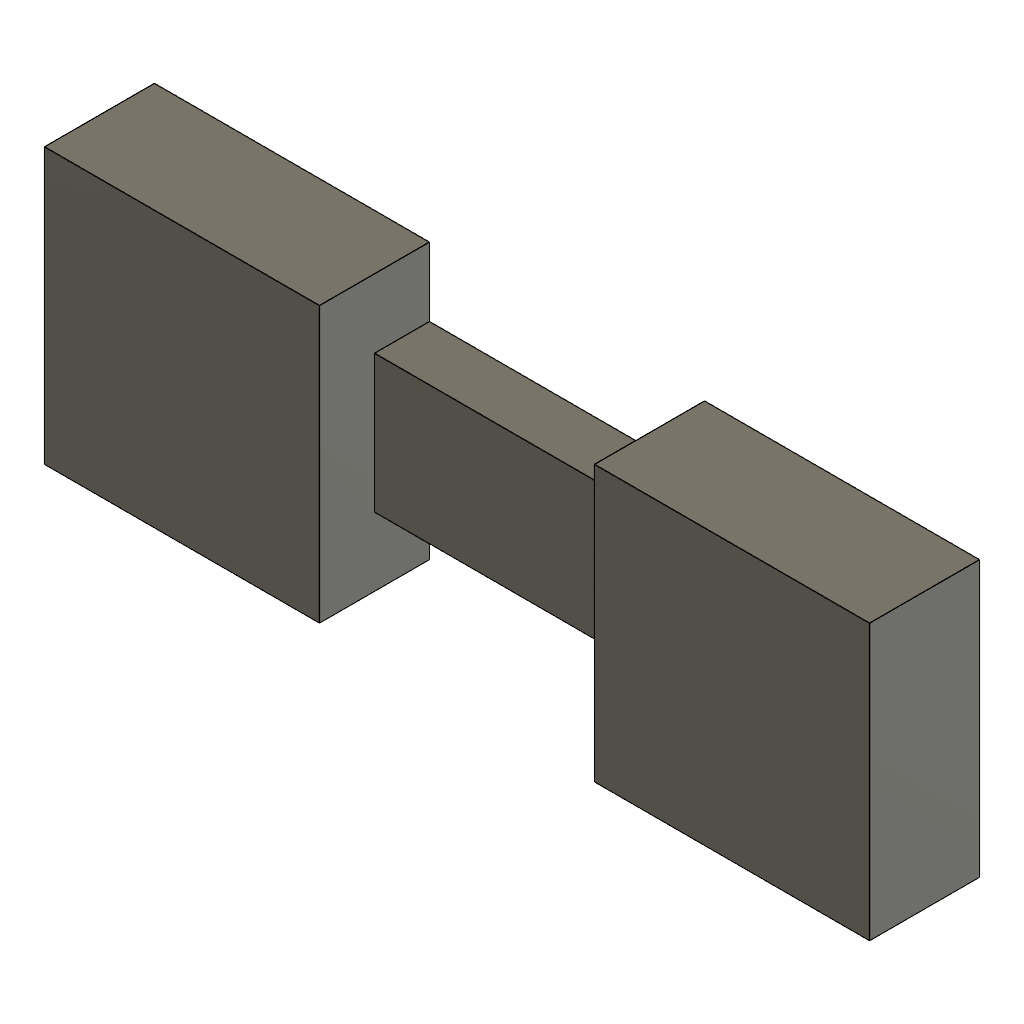
join_bridge (Autodesk Fusion 360 design; units mm, degrees)
part number: 2026-11-10-15-06-50-761
Autodesk Fusion 360 part; units mm, degrees
sketch "Sketch1" plane through (0, 0, 0) normal (0, 0, 1) x (1, 0, 0)
  line L0 (0, 0) -> (10, 0)
  line L1 (10, 0) -> (10, 10)
  line L2 (10, 10) -> (0, 10)
  line L3 (0, 10) -> (0, 0)
extrude "Extrude1" add sketch "Sketch1" along normal blind 4 makes body 1
sketch "Sketch2" plane through (0, 0, 0) normal (0, 0, 1) x (1, 0, 0)
  line L0 (20, 0) -> (30, 0)
  line L1 (30, 0) -> (30, 10)
  line L2 (30, 10) -> (20, 10)
  line L3 (20, 10) -> (20, 0)
extrude "Extrude2" add sketch "Sketch2" along normal blind 4 separate body makes body 2
sketch "Sketch3" plane through (0, 0, 0) normal (0, 0, 1) x (1, 0, 0)
  line L0 (5, 2.5) -> (25, 2.5)
  line L1 (25, 2.5) -> (25, 7.5)
  line L2 (25, 7.5) -> (5, 7.5)
  line L3 (5, 7.5) -> (5, 2.5)
extrude "Extrude3" add sketch "Sketch3" along normal blind 2 bodies 1 2
